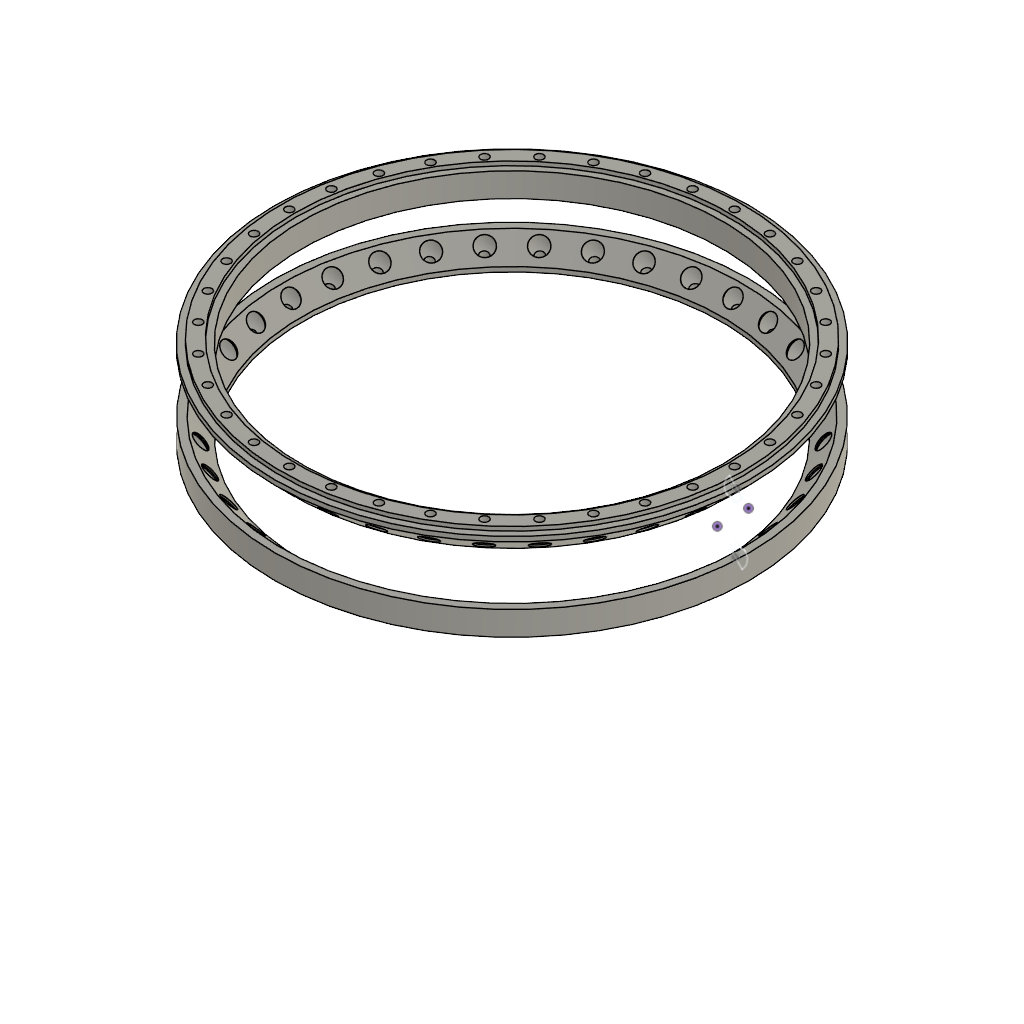
Robot_Assembly (Autodesk Fusion 360 archive; units mm, degrees)
design "Loziska"
part number: 2026-11-02-19-01-56-183
part number: 2026-11-02-19-01-56-425
part number: 2026-11-02-19-01-57-037
Autodesk Fusion 360 part; units mm, degrees
sketch "SK_Krouzek_dolni_telo" plane through (0, 0, 0) normal (0, 1, 0) x (1, 0, 0) in component "Krouzek_dolni"
  line L0 (53.5, -42) -> (57, -42)
  line L1 (57, -42) -> (57, -43)
  line L2 (57, -43) -> (58.55, -43)
  line L3 (58.55, -43) -> (58.55, -48.9576)
  line L4 (58.55, -48.9576) -> (56.6977, -48.9576)
  line L5 (56.6977, -48.9576) -> (51.9, -44.1598)
  line L6 (51.9, -44.1598) -> (51.9, -43)
  line L7 (51.9, -43) -> (53.5, -43)
  line L8 (53.5, -43) -> (53.5, -42)
  line L9 (0, -1.75) -> (0, -22.5) construction
  dimension "d22" = 53.5
  dimension "d23" = 42
  dimension "d24" = 57
  dimension "d25" = 57
  dimension "d26" = 43
  dimension "d27" = 58.55
  dimension "d28" = 43
  dimension "d29" = 58.55
  dimension "d30" = 48.9576
  dimension "d31" = 56.6977
  dimension "d32" = 48.9576
  dimension "d33" = 51.9
  dimension "d34" = 44.1598
  dimension "d35" = 51.9
  dimension "d36" = 43
  dimension "d37" = 43
  measures "d22" horizontal distance of origin L0.start
  measures "d23" vertical distance of origin L0.start
  measures "d24" horizontal distance of origin L0.end
  measures "d25" horizontal distance of origin L1.end
  measures "d26" vertical distance of origin L1.end
  measures "d27" horizontal distance of origin L2.end
  measures "d28" vertical distance of origin L2.end
  measures "d29" horizontal distance of origin L3.end
  measures "d30" vertical distance of origin L3.end
  measures "d31" horizontal distance of origin L4.end
  measures "d32" vertical distance of origin L4.end
  measures "d33" horizontal distance of origin L5.end
  measures "d34" vertical distance of origin L5.end
  measures "d35" horizontal distance of origin L6.end
  measures "d36" vertical distance of origin L6.end
  measures "d37" vertical distance of origin L7.end
revolve "Krouzek_dolni_telo" add sketch "SK_Krouzek_dolni_telo" angle 360 about axis through (0, 0, 1.75) along (0, 0, 1) makes body 1 in component "Krouzek_dolni"
sketch "SK_Krouzek_horni_telo" plane through (0, 0, 0) normal (0, 1, 0) x (1, 0, 0) in component "Krouzek_horni"
  line L0 (57, -65.6) -> (53.5, -65.6)
  line L1 (53.5, -65.6) -> (53.5, -64.6)
  line L2 (53.5, -64.6) -> (51.95, -64.6)
  line L3 (51.95, -64.6) -> (51.95, -58.6424)
  line L4 (51.95, -58.6424) -> (53.8023, -58.6424)
  line L5 (53.8023, -58.6424) -> (58.6, -63.4402)
  line L6 (58.6, -63.4402) -> (58.6, -64.6)
  line L7 (58.6, -64.6) -> (57, -64.6)
  line L8 (57, -64.6) -> (57, -65.6)
  line L9 (0, -1.75) -> (0, -22.5) construction
  dimension "d47" = 57
  dimension "d48" = 65.6
  dimension "d49" = 53.5
  dimension "d50" = 53.5
  dimension "d51" = 64.6
  dimension "d52" = 51.95
  dimension "d53" = 64.6
  dimension "d54" = 51.95
  dimension "d55" = 58.6424
  dimension "d56" = 53.8023
  dimension "d57" = 58.6424
  dimension "d58" = 58.6
  dimension "d59" = 63.4402
  dimension "d60" = 58.6
  dimension "d61" = 64.6
  dimension "d62" = 64.6
  measures "d47" horizontal distance of origin L0.start
  measures "d48" vertical distance of origin L0.start
  measures "d49" horizontal distance of origin L0.end
  measures "d50" horizontal distance of origin L1.end
  measures "d51" vertical distance of origin L1.end
  measures "d52" horizontal distance of origin L2.end
  measures "d53" vertical distance of origin L2.end
  measures "d54" horizontal distance of origin L3.end
  measures "d55" vertical distance of origin L3.end
  measures "d56" horizontal distance of origin L4.end
  measures "d57" vertical distance of origin L4.end
  measures "d58" horizontal distance of origin L5.end
  measures "d59" vertical distance of origin L5.end
  measures "d60" horizontal distance of origin L6.end
  measures "d61" vertical distance of origin L6.end
  measures "d62" vertical distance of origin L7.end
revolve "Krouzek_horni_telo" add sketch "SK_Krouzek_horni_telo" angle 360 about axis through (0, 0, 1.75) along (0, 0, 1) separate body makes body 2 in component "Krouzek_horni"
ref_plane "WorkPlane2" through (0, 0, 42) normal (0, 0, 1) x (1, 0, 0) in component "Krouzek_dolni"
sketch "SK_Vytlac" plane through (0, 0, 42) normal (0, 0, 1) x (1, 0, 0) in component "Krouzek_dolni"
  line L0 (0, 0) -> (55.55, 0) construction
  circle A0 centre (55.55, 0) radius 1
  dimension "d91" = 2
  dimension "d92" = 55.55
  constraint horizontal L0
  measures "d91" diameter of A0
  measures "d92" horizontal distance of L0.start L0.end
extrude "Vytlac_otvor" cut sketch "SK_Vytlac" along normal blind 4.18 bodies 1 in component "Krouzek_dolni"
pattern_circular "Vytlac_pole" count 36 over 360 about axis through (0, 0, 1.75) along (0, 0, 1) of "Vytlac_otvor" in component "Krouzek_dolni"
ref_plane "WorkPlane2" through (0, 0, 65.6) normal (0, 0, 1) x (1, 0, 0) in component "Krouzek_horni"
sketch "SK_Vytlac (2)" plane through (0, 0, 65.6) normal (0, 0, 1) x (1, 0, 0) in component "Krouzek_horni"
  line L0 (0, 0) -> (54.95, 0) construction
  circle A0 centre (54.95, 0) radius 1
  dimension "d99" = 2
  dimension "d100" = 54.95
  constraint horizontal L0
  measures "d99" diameter of A0
  measures "d100" horizontal distance of L0.start L0.end
extrude "Vytlac_otvor'" cut sketch "SK_Vytlac (2)" against normal blind 4.18 bodies 2 in component "Krouzek_horni"
pattern_circular "Vytlac_pole'" count 36 over 360 about axis through (0, 0, 1.75) along (0, 0, 1) of "Vytlac_otvor'" in component "Krouzek_horni"
ref_plane "WorkPlane3" through (0, 12.125, 0) normal (0.707107, 0, 0.707107) x (0, 1, 0) in component "Krouzek_dolni"
ref_plane "WorkPlane4" through (50.6788, 12.125, 50.6788) normal (0.707107, 0, 0.707107) x (0, 1, 0) in component "Krouzek_dolni"
sketch "SK_Kapsa_dolni" plane through (50.6788, 0, 50.6788) normal (0.707107, 0, 0.707107) x (0, 1, 0) in component "Krouzek_dolni"
  arc A0 (0, -8.6447) -> (2.48, -6.1647) centre (0, -6.1647) ccw
  line L0 (2.48, -6.1647) -> (2.48, -5.9031)
  line L1 (2.48, -5.9031) -> (2.05, -5.4731)
  line L2 (2.05, -5.4731) -> (2.05, -3.9731)
  line L3 (2.05, -3.9731) -> (0, -3.9731)
  line L4 (0, -3.9731) -> (0, -8.6447)
  dimension "d183" = 2.48
  dimension "d184" = 6.1647
  dimension "d187" = 2.05
  dimension "d231" = 0.2616
  dimension "d232" = 0.6916
  dimension "d233" = 2.1916
  constraint vertical L4
  constraint coincident A0.centre L4
  constraint tangent A0 L0
  constraint vertical L2
  constraint horizontal L3
  constraint coincident origin L4
  constraint vertical L0
  measures "d183" radius of A0
  measures "d184" vertical distance of origin A0.centre
  measures "d187" horizontal distance of origin L1.end
  measures "d231" vertical distance of A0.centre L0.end
  measures "d232" vertical distance of A0.centre L1.end
  measures "d233" vertical distance of A0.centre L3.end
revolve "Kapsa_dolni" cut sketch "SK_Kapsa_dolni" angle 360 about axis through (53.4882, 0, 47.8694) along (0.707107, 0, -0.707107) bodies 1 in component "Krouzek_dolni"
pattern_circular "Kapsy_pole" count 36 over 360 about axis through (0, 0, 1.75) along (0, 0, 1) of "Kapsa_dolni" in component "Krouzek_dolni"
ref_plane "WorkPlane3" through (0, 12.125, 0) normal (0.707107, 0, 0.707107) x (0, 1, 0) in component "Krouzek_horni"
ref_plane "WorkPlane4" through (58.3712, 12.125, 58.3712) normal (0.707107, 0, 0.707107) x (0, 1, 0) in component "Krouzek_horni"
sketch "SK_Kapsa_horni" plane through (58.3712, 0, 58.3712) normal (0.707107, 0, 0.707107) x (0, 1, 0) in component "Krouzek_horni"
  arc A0 (0, 6.5941) -> (-2.48, 4.1141) centre (0, 4.1141) ccw
  line L0 (-2.48, 4.1141) -> (-2.48, 3.8525)
  line L1 (-2.48, 3.8525) -> (-2.05, 3.4225)
  line L2 (-2.05, 3.4225) -> (-2.05, 1.9225)
  line L3 (-2.05, 1.9225) -> (0, 1.9225)
  line L4 (0, 1.9225) -> (0, 6.5941)
  dimension "d196" = 2.48
  dimension "d197" = 4.1141
  dimension "d200" = 2.05
  dimension "d234" = 0.2616
  dimension "d235" = 0.6916
  dimension "d236" = 2.1916
  constraint vertical L4
  constraint coincident A0.centre L4
  constraint tangent A0 L0
  constraint vertical L2
  constraint horizontal L3
  constraint coincident origin L4
  constraint vertical L0
  measures "d196" radius of A0
  measures "d197" vertical distance of origin A0.centre
  measures "d200" horizontal distance of origin L1.end
  measures "d234" vertical distance of A0.centre L0.end
  measures "d235" vertical distance of A0.centre L1.end
  measures "d236" vertical distance of A0.centre L3.end
revolve "Kapsa_horni" cut sketch "SK_Kapsa_horni" angle 360 about axis through (57.0118, 0, 59.7306) along (-0.707107, 0, 0.707107) bodies 2 in component "Krouzek_horni"
pattern_circular "Kapsy_pole'" count 36 over 360 about axis through (0, 0, 1.75) along (0, 0, 1) of "Kapsa_horni" in component "Krouzek_horni"
component "Krouzek_dolni" placed x (1, 0, 0) y (0, 1, 0) z (0, 0, 1) at (0, 0, 0)
component "Krouzek_horni" placed x (1, 0, 0) y (0, 1, 0) z (0, 0, 1) at (0, 0, 0)
equation "seat_plane_z = 42 mm" comment "dno drazky v Sedlu loziska (Base 2)"
equation "upper_seat_z = 65.6 mm" comment "dno drazky v Krytu hornim (Base 2)"
equation "ring_groove_d = 1 mm" comment "hloubka drazky = vyska jazyku krouzku"
equation "ring_id = 107 mm" comment "vnitrni prumer jazyku (drazka 106.4)"
equation "ring_wall = 3.5 mm" comment "sirka jazyku (drazka 4.1)"
equation "ball_d = 4.36 mm" comment "skutecny (namereny) prumer kulicky; drahy se nemeni, kapsy se prizpusobi"
equation "KrouzekDnoKapsy = 2 mm" comment "dno kapsy pro navrhovou kulicku DrahaBallD od dna drazky -> urcuje polohu drah v Base"
equation "KapsaVule = 0.6 mm" comment "vule kulove kapsy na prumer (kulicka se v kapse volne otaci)"
equation "KrouzekVule = KulickaR - KapsaUstiH" comment "kolma vule krouzek-draha = vycnivani kulicky lezici na dne kapsy"
equation "KrouzekVnitrR = 51.9 mm" comment "vnitrni polomer tela krouzku (dolni); horni zrcadlove"
equation "KrouzekVnejsiR = 58.55 mm" comment "vnejsi polomer tela krouzku (dolni); srouby M5 krytu od r 60.5"
equation "KrouzekPlochaNadStredem = 2.85 mm" comment "rovna cast nad stredem kulicky (strop kapsy min. 0.6 mm)"
equation "KulickyN = 36" comment "pocet kulicek v krouzku"
equation "KuzelUhel = 45 deg" comment "sklon drah (vzorce plati pro 45 st.)"
equation "KulickaR = ball_d / 2"
equation "KulickaDrahaR = ring_id / 2 + ring_wall / 2" comment "polomer drahy stredu kulicek"
equation "KulickaDolniZ = KulickaDrahaR + DrahaDolniC - KulickaR * sqrt(2)" comment "stred dolnich kulicek: kulicka ball_d se dotyka drahy rotoru (na polomeru KulickaDrahaR)"
equation "KulickaHorniZ = 2 * StredZ - KulickaDolniZ" comment "stred hornich kulicek, zrcadlove k dolnim (draha veze je zrcadlem drahy rotoru)"
equation "StredZ = ( seat_plane_z + upper_seat_z ) / 2" comment "stred symetrie dolni/horni krouzek"
equation "DrahaDolniC = seat_plane_z + KrouzekDnoKapsy + DrahaBallD / 2 - KulickaDrahaR + DrahaBallD / 2 * sqrt(2)" comment "draha rotoru z = r + C, pevne podle Base (kulicka DrahaBallD s dnem DrahaBallD/2 + KrouzekDnoKapsy nad drazkou)"
equation "KrouzekDolniC = DrahaDolniC - KrouzekVule * sqrt(2)" comment "horni plocha dolniho krouzku z = r + C"
equation "d22 = ring_id / 2"
equation "d23 = seat_plane_z"
equation "d24 = ring_id / 2 + ring_wall"
equation "d25 = ring_id / 2 + ring_wall"
equation "d26 = seat_plane_z + ring_groove_d"
equation "d27 = KrouzekVnejsiR"
equation "d28 = seat_plane_z + ring_groove_d"
equation "d29 = KrouzekVnejsiR"
equation "d30 = KulickaDolniZ + KrouzekPlochaNadStredem"
equation "d31 = KulickaDolniZ + KrouzekPlochaNadStredem - KrouzekDolniC"
equation "d32 = KulickaDolniZ + KrouzekPlochaNadStredem"
equation "d33 = KrouzekVnitrR"
equation "d34 = KrouzekVnitrR + KrouzekDolniC"
equation "d35 = KrouzekVnitrR"
equation "d36 = seat_plane_z + ring_groove_d"
equation "d37 = seat_plane_z + ring_groove_d"
equation "d47 = 2 * KulickaDrahaR - ( ring_id / 2 )"
equation "d48 = 2 * StredZ - ( seat_plane_z )"
equation "d49 = 2 * KulickaDrahaR - ( ring_id / 2 + ring_wall )"
equation "d50 = 2 * KulickaDrahaR - ( ring_id / 2 + ring_wall )"
equation "d51 = 2 * StredZ - ( seat_plane_z + ring_groove_d )"
equation "d52 = 2 * KulickaDrahaR - ( KrouzekVnejsiR )"
equation "d53 = 2 * StredZ - ( seat_plane_z + ring_groove_d )"
equation "d54 = 2 * KulickaDrahaR - ( KrouzekVnejsiR )"
equation "d55 = 2 * StredZ - ( KulickaDolniZ + KrouzekPlochaNadStredem )"
equation "d56 = 2 * KulickaDrahaR - ( KulickaDolniZ + KrouzekPlochaNadStredem - KrouzekDolniC )"
equation "d57 = 2 * StredZ - ( KulickaDolniZ + KrouzekPlochaNadStredem )"
equation "d58 = 2 * KulickaDrahaR - ( KrouzekVnitrR )"
equation "d59 = 2 * StredZ - ( KrouzekVnitrR + KrouzekDolniC )"
equation "d60 = 2 * KulickaDrahaR - ( KrouzekVnitrR )"
equation "d61 = 2 * StredZ - ( seat_plane_z + ring_groove_d )"
equation "d62 = 2 * StredZ - ( seat_plane_z + ring_groove_d )"
equation "UstiD = 4.1 mm" comment "prumer usti (hrana limce): kulicka se nacvakne, jde vytlacit"
equation "KapsaPosun = KapsaVule / 2" comment "stred kuloveho dna kapsy posunuty od stredu kulicky k draze (dno se dotyka kulicky)"
equation "VytlacD = 2 mm" comment "otvor ze spodu jazyku pro vytlaceni kulicky (spendlik/kancelarska sponka)"
equation "VytlacR = KulickaDrahaR + 0.3 mm" comment "polomer osy otvoru pro vytlaceni (mimo misto dotyku kulicka-dno)"
equation "d89 = seat_plane_z"
equation "d91 = VytlacD"
equation "d92 = VytlacR"
equation "d93 = KrouzekDnoKapsy + KulickaR"
equation "d95 = KulickyN"
equation "d97 = upper_seat_z"
equation "d99 = VytlacD"
equation "d100 = 2 * KulickaDrahaR - VytlacR"
equation "d101 = -( KrouzekDnoKapsy + KulickaR )"
equation "d103 = KulickyN"
equation "DrahaBallD = 4.3 mm" comment "navrhovy prumer kulicky, podle ktereho jsou drahy v Base_2_gears (ball_d tam = 4.3); NEMENIT bez zmeny Base"
equation "KapsaZdvih = 0.25 mm" comment "o kolik muze kulicka odjet ode dna kapsy k limci (vule k limci v provozu)"
equation "KapsaUstiH = KapsaZdvih + sqrt(KulickaR ^ 2 - ( UstiD / 2 ) ^ 2)" comment "rovina usti (plocha krouzku) od stredu kulicky ve smeru k draze"
equation "KapsaNadUsti = 1.5 mm" comment "presah rezu kapsy nad usti (jen vzduch)"
equation "d181 = ( KulickaDrahaR + KulickaDolniZ ) / sqrt(2)"
equation "d183 = ( ball_d + KapsaVule ) / 2"
equation "d184 = ( KulickaDrahaR - KulickaDolniZ ) / sqrt(2) - ( KapsaPosun )"
equation "d187 = UstiD / 2"
equation "d190 = KulickyN"
equation "d194 = ( KulickaDrahaR + KulickaHorniZ ) / sqrt(2)"
equation "d196 = ( ball_d + KapsaVule ) / 2"
equation "d197 = ( KulickaHorniZ - KulickaDrahaR ) / sqrt(2) - ( KapsaPosun )"
equation "d200 = UstiD / 2"
equation "d203 = KulickyN"
equation "d231 = KapsaUstiH - ( ( ball_d + KapsaVule ) / 2 - UstiD / 2 ) - KapsaPosun"
equation "d232 = KapsaUstiH - KapsaPosun"
equation "d233 = KapsaUstiH + KapsaNadUsti - KapsaPosun"
equation "d234 = KapsaUstiH - ( ( ball_d + KapsaVule ) / 2 - UstiD / 2 ) - KapsaPosun"
equation "d235 = KapsaUstiH - KapsaPosun"
equation "d236 = KapsaUstiH + KapsaNadUsti - KapsaPosun"
named bodies: "Krouzek_dolni", "Krouzek_horni"

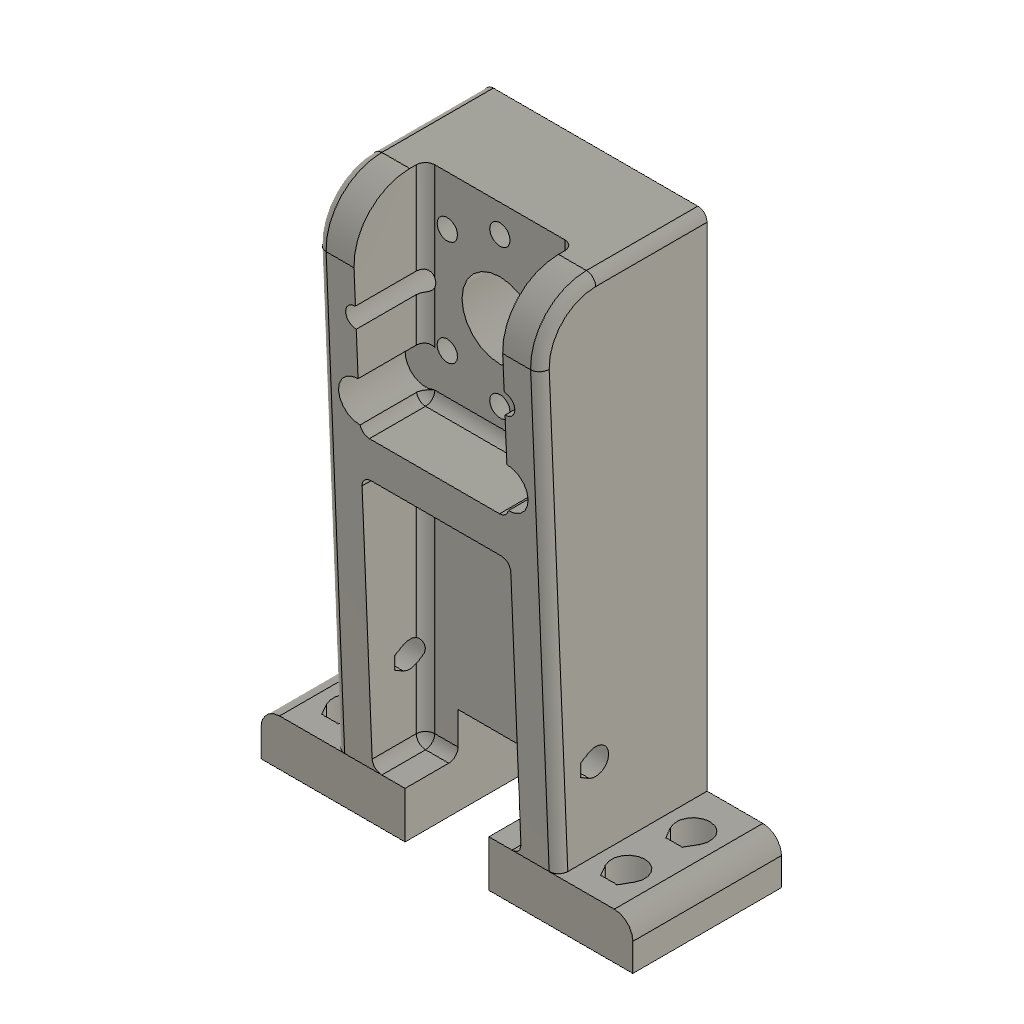
design "PenMountLink_V2"
Autodesk Fusion 360 part; units mm, degrees
sketch "SK_Zakladna" plane through (0, 0, 0) normal (0, 0, 1) x (1, 0, 0)
  line L0 (-20, -8) -> (20, -8)
  line L1 (20, -8) -> (20, 8)
  line L2 (20, 8) -> (-20, 8)
  line L3 (-20, 8) -> (-20, -8)
  dimension "d106" = 20
  dimension "d107" = 8
  dimension "d108" = 20
  dimension "d109" = 8
  constraint horizontal L0
  constraint vertical L1
  constraint horizontal L2
  constraint vertical L3
  measures "d106" horizontal distance of origin L0.start
  measures "d107" vertical distance of origin L0.start
  measures "d108" horizontal distance of origin L1.end
  measures "d109" vertical distance of origin L1.end
extrude "Zakladna" add sketch "SK_Zakladna" along normal blind 5
sketch "SK_Sloupek" plane through (0, 0, 0) normal (1, 0, 0) x (0, 0, -1)
  arc A0 (-59, -4) -> (-52.7496, -9.9948) centre (-53, -4) ccw
  line L0 (-5, 8) -> (-5, -8)
  line L1 (-5, -8) -> (-52.7496, -9.9948)
  line L2 (-59, -4) -> (-59, 8)
  line L3 (-59, 8) -> (-5, 8)
  dimension "d112" = 8
  dimension "d113" = 5
  dimension "d114" = 8
  dimension "d115" = 59
  dimension "d116" = 6
  dimension "d117" = 4
  constraint vertical L0
  constraint vertical L2
  constraint horizontal L3
  constraint tangent A0 L1
  constraint tangent A0 L2
  measures "d112" vertical distance of origin L0.start
  measures "d113" horizontal distance of origin L0.start
  measures "d114" vertical distance of origin L0.end
  measures "d115" horizontal distance of origin L2.end
  measures "d116" radius of A0
  measures "d117" vertical distance of origin A0.centre
extrude "Sloupek" add sketch "SK_Sloupek" along normal mid plane 24
sketch "SK_Kapsa" plane through (0, 0, 0) normal (0, 0, 1) x (1, 0, 0)
  line L0 (-8, -28) -> (8, -28)
  line L1 (8, -28) -> (8, -2.3)
  line L2 (8, -2.3) -> (-8, -2.3)
  line L3 (-8, -2.3) -> (-8, -28)
  dimension "d120" = 8
  dimension "d121" = 28
  dimension "d122" = 8
  dimension "d123" = -2.3
  constraint horizontal L0
  constraint vertical L1
  constraint horizontal L2
  constraint vertical L3
  measures "d120" horizontal distance of origin L0.start
  measures "d121" vertical distance of origin L0.start
  measures "d122" horizontal distance of origin L1.end
  measures "d123" vertical distance of origin L1.end
extrude "Kapsa_horni" cut sketch "SK_Kapsa" along normal through all from surface at 37
sketch "SK_Horn" plane through (0, 0, 0) normal (0, 1, 0) x (1, 0, 0)
  line L0 (0, 0) -> (0, -48) construction
  circle A0 centre (0, -48) radius 4.075
  line L1 (0, -48) -> (8, -48) construction
  line L2 (0, -48) -> (5.6569, -53.6569) construction
  circle A1 centre (5.6569, -53.6569) radius 1.1
  circle A2 centre (-5.6569, -53.6569) radius 1.1
  circle A3 centre (-5.6569, -42.3431) radius 1.1
  circle A4 centre (5.6569, -42.3431) radius 1.1
  dimension "d126" = 48
  dimension "d127" = 8.15
  dimension "d128" = 8
  dimension "d129" = 8
  dimension "d130" = 45
  dimension "d131" = 2.2
  constraint vertical L0
  constraint horizontal L1
  constraint equal A1 A2
  constraint equal A1 A3
  constraint equal A1 A4
  constraint symmetric L0 L2.end A2.centre
  constraint symmetric L1 A2.centre A3.centre
  constraint symmetric L1 L2.end A4.centre
  measures "d126" vertical distance of L0.start L0.end
  measures "d127" diameter of A0
  measures "d128" distance of L0.end L1.end
  measures "d129" distance of L0.end L2.end
  measures "d130" angle of L1 L2
  measures "d131" diameter of A1
extrude "Diry_horn" cut sketch "SK_Horn" along normal mid plane 26
sketch "SK_Diry_zavazi" plane through (0, 0, 0) normal (1, 0, 0) x (0, 0, -1)
  arc A0 (-12.5376, -4.7) -> (-14.9624, -4.7) centre (-13.75, -4) ccw
  line L0 (-14.9624, -4.7) -> (-14.437, -5.61)
  line L1 (-12.5376, -4.7) -> (-13.063, -5.61)
  line L2 (-14.437, -5.61) -> (-13.063, -5.61)
  line L3 (-13.75, -4) -> (-13.75, -5.61) construction
  dimension "d134" = 4
  dimension "d135" = 13.75
  dimension "d136" = 1.4
  dimension "d137" = 1.61
  dimension "d138" = 30
  constraint tangent A0 L0
  constraint tangent A0 L1
  constraint midpoint L2 L3.end
  constraint perpendicular L2 L3
  constraint vertical L3
  measures "d134" vertical distance of origin A0.centre
  measures "d135" horizontal distance of origin A0.centre
  measures "d136" radius of A0
  measures "d137" distance of A0.centre L3.end
  measures "d138" angle of L0 L3
extrude "Diry_zavazi" cut sketch "SK_Diry_zavazi" along normal mid plane 34
sketch "SK_Diry_zakladna" plane through (0, 0, 0) normal (0, 0, 1) x (1, 0, 0)
  arc A0 (-13.4412, -4.4) -> (-16.5588, -4.4) centre (-15, -3.5) ccw
  line L0 (-16.5588, -4.4) -> (-15.8833, -5.57)
  line L1 (-13.4412, -4.4) -> (-14.1167, -5.57)
  line L2 (-15.8833, -5.57) -> (-14.1167, -5.57)
  line L3 (-15, -3.5) -> (-15, -5.57) construction
  dimension "d141" = 15
  dimension "d142" = 3.5
  dimension "d143" = 1.8
  dimension "d144" = 2.07
  dimension "d145" = 30
  constraint tangent A0 L0
  constraint tangent A0 L1
  constraint midpoint L2 L3.end
  constraint perpendicular L2 L3
  constraint vertical L3
  measures "d141" horizontal distance of origin A0.centre
  measures "d142" vertical distance of origin A0.centre
  measures "d143" radius of A0
  measures "d144" distance of A0.centre L3.end
  measures "d145" angle of L0 L3
extrude "Dira_zakladna" cut sketch "SK_Diry_zakladna" along normal blind 6
pattern_linear "Diry_zakladna_pole" count 2 spacing 30 along (1, 0, 0) count 2 spacing 7 along (0, 1, 0) of "Dira_zakladna"
fillet "Usi_obvod_R" radius 1 6 edges at (-12, 2, 59) (-12, -8.3303, 57.1532) (-12, -8.9974, 28.8748) (12, 2, 59) (12, -8.3303, 57.1532) (12, -8.9974, 28.8748)
fillet "Zakladna_hrany_R" radius 2 2 edges at (-20, 0, 5) (20, 0, 5)
extrude "Kapsa_dolni" cut sketch "SK_Kapsa" along normal blind 28 from surface at 5
fillet "Kapsy_kouty_R" radius 1 13 edges at (8, -5.7349, 33) (8, -2.3, 19) (8, -5.15, 5) (0, -2.3, 5) (-8, -5.15, 5) (0, -2.3, 33) (-8, -2.3, 19) (-8, -5.7349, 33) (8, -2.3, 48) (8, -5.8184, 37) (0, -2.3, 37) (-8, -5.8184, 37) (-8, -2.3, 48)
sketch "SK_Horn_8" plane through (0, 0, 0) normal (0, 1, 0) x (1, 0, 0)
  circle A0 centre (8, -48) radius 1.1
  circle A1 centre (0, -56) radius 1.1
  circle A2 centre (-8, -48) radius 1.1
  circle A3 centre (0, -40) radius 1.1
  line L0 (0, -48) -> (8, -48) construction
  line L1 (0, -48) -> (0, -56) construction
  line L2 (0, -48) -> (-8, -48) construction
  line L3 (0, -48) -> (0, -40) construction
  dimension "d170" = 2.2
  dimension "d171" = 2.2
  dimension "d172" = 2.2
  dimension "d173" = 2.2
  dimension "d174" = 48
  dimension "d175" = 8
  dimension "d176" = 8
  dimension "d177" = 8
  dimension "d178" = 8
  constraint horizontal L0
  constraint vertical L1
  constraint horizontal L2
  constraint vertical L3
  measures "d170" diameter of A0
  measures "d171" diameter of A1
  measures "d172" diameter of A2
  measures "d173" diameter of A3
  measures "d174" vertical distance of origin L0.start
  measures "d175" horizontal distance of L0.start A0.centre
  measures "d176" vertical distance of L0.start A1.centre
  measures "d177" horizontal distance of L0.start A2.centre
  measures "d178" vertical distance of L0.start A3.centre
extrude "Diry_horn_8" cut sketch "SK_Horn_8" along normal mid plane 26
sketch "Sketch16" plane through (0, 8, 0) normal (0, 1, 0) x (-1, 0, 0)
  circle A0 centre (5.6569, 42.3431) radius 1.1
  circle A1 centre (5.6569, 53.6569) radius 1.1
  circle A2 centre (-5.6569, 53.6569) radius 1.1
  circle A3 centre (0, 48) radius 4.075
  circle A4 centre (-5.6569, 42.3431) radius 1.1
  arc A5 (-18, 5) -> (-20, 3) centre (-18, 3) ccw
  line L0 (-20, 3) -> (-20, 0)
  line L1 (-20, 0) -> (20, 0)
  line L2 (20, 0) -> (20, 3)
  arc A6 (20, 3) -> (18, 5) centre (18, 3) ccw
  line L3 (18, 5) -> (12, 5)
  line L4 (12, 5) -> (12, 58)
  arc A7 (12, 58) -> (11, 59) centre (11, 58) ccw
  line L5 (11, 59) -> (-11, 59)
  arc A8 (-11, 59) -> (-12, 58) centre (-11, 58) ccw
  line L6 (-12, 58) -> (-12, 5)
  line L7 (-12, 5) -> (-18, 5)
  line L8 (4.5, 9.5) -> (-4.5, 9.5)
  line L9 (-4.5, 9.5) -> (-4.5, -9.5)
  line L10 (-4.5, -9.5) -> (4.5, -9.5)
  line L11 (4.5, -9.5) -> (4.5, 9.5)
  line L12 (4.5, 9.5) -> (-4.5, -9.5) construction
  line L13 (-4.5, 9.5) -> (4.5, -9.5) construction
  circle A9 centre (0, 40) radius 1.1
  circle A10 centre (-8, 48) radius 1.1
  circle A11 centre (0, 56) radius 1.1
  circle A12 centre (8, 48) radius 1.1
  dimension "d167" = 9
  dimension "d168" = 19
  constraint horizontal L8
  constraint perpendicular L8 L9
  constraint parallel L8 L10
  constraint parallel L9 L11
  constraint coincident L12 origin
  constraint coincident L13 origin
  measures "d167" distance of L9.end L10.end
  measures "d168" distance of L8.end L9.end
extrude "Extrude13" cut sketch "Sketch16" against normal through all contours L1 L8 L9 L11
ref_plane "WorkPlane1" through (0, -2.3, 0) normal (0, 1, 0) x (0, 0, 1)
sketch "SK_Horn_8_hlavy" plane through (0, -2.3, 0) normal (0, 1, 0) x (1, 0, 0)
  circle A0 centre (8, -40) radius 2.2
  circle A1 centre (-8, -40) radius 2.2
  dimension "d186" = 4.4
  dimension "d187" = 4.4
  measures "d186" diameter of A0
  measures "d187" diameter of A1
extrude "Diry_horn_8_hlavy" cut sketch "SK_Horn_8_hlavy" against normal blind 21
equation "AxisOffset = 48 mm" comment "Osa motoru (horn) od dosedaci plochy zakladny z=0"
equation "BaseL = 40 mm" comment "Delka zakladny (X)"
equation "BaseD = 16 mm" comment "Hloubka zakladny (Y)"
equation "BaseT = 5 mm" comment "Tloustka zakladny"
equation "BaseHoleD = 3.6 mm" comment "Diry zakladny (M3)"
equation "BaseHoleX = 30 mm" comment "Roztec der zakladny X"
equation "BaseHoleY = 7 mm" comment "Roztec der zakladny Y"
equation "ColW = 24 mm" comment "Sirka sloupku (X)"
equation "ColD = BaseD" comment "Hloubka sloupku (Y)"
equation "WallT = 10.3 mm" comment "Stena hornu"
equation "PocketW = 16 mm" comment "Sirka kapsy na hlavy sroubu"
equation "ColTopAboveAxis = WeightHoleDZ + EarCornerR" comment "Vrsek sloupku nad osou"
equation "ColTopZ = AxisOffset + ColTopAboveAxis" comment "Vyska sloupku"
equation "EarCornerR = 6 mm" comment "Polomer predniho horniho rohu ucha"
equation "EarFrontExt = EarCornerR - ( WeightHoleFromHorn - ColD / 2 )" comment "Presah ucha pred celo zakladny"
equation "PocketBelowAxis = 11 mm" comment "Dno horni kapsy pod osou"
equation "HornCenterD = 8.15 mm" comment "Stredova dira hornu"
equation "HornHoleD = 2.2 mm" comment "Diry sroubu hornu M2"
equation "HornPCD = 16 mm" comment "Roztecna kruznice sroubu hornu"
equation "HornHoleCham = 0.5 mm" comment "Srazeni der hornu v kapse"
equation "WeightHoleD = 2.8 mm" comment "Diry pro zavazi"
equation "WeightHoleFromHorn = 12 mm" comment "Diry zavazi: vzdalenost pred celem hornu"
equation "WeightHoleDZ = 5 mm" comment "Diry zavazi: posun nad osou"
equation "TdHalfAngle = 30 deg" comment "Slzicka: polovicni uhel spicky"
equation "TdCapRatio = 1.15" comment "Slzicka: vzdalenost useku spicky / polomer"
equation "R_EarOuter = 1 mm" comment "Zaobleni vnejsiho obvodu usi"
equation "R_ColRoot = 1 mm" comment "Zaobleni korene sloupku"
equation "R_BaseEdge = 2 mm" comment "Zaobleni hran zakladny"
equation "d106 = BaseL / 2"
equation "d107 = BaseD / 2"
equation "d108 = BaseL / 2"
equation "d109 = BaseD / 2"
equation "d110 = BaseT"
equation "d112 = ColD / 2"
equation "d113 = BaseT"
equation "d114 = ColD / 2"
equation "d115 = ColTopZ"
equation "d116 = EarCornerR"
equation "d117 = ColD / 2 + EarFrontExt - EarCornerR"
equation "d118 = ColW"
equation "d120 = PocketW / 2"
equation "d121 = ColD / 2 + 20 mm"
equation "d122 = PocketW / 2"
equation "d123 = ColD / 2 - WallT"
equation "d124 = AxisOffset - PocketBelowAxis"
equation "d126 = AxisOffset"
equation "d127 = HornCenterD"
equation "d128 = HornPCD / 2"
equation "d129 = HornPCD / 2"
equation "d131 = HornHoleD"
equation "d132 = ColD + 10 mm"
equation "d134 = WeightHoleFromHorn - ColD / 2"
equation "d136 = WeightHoleD / 2"
equation "d137 = ( WeightHoleD / 2 ) * TdCapRatio"
equation "d138 = TdHalfAngle"
equation "d139 = ColW + 10 mm"
equation "d141 = BaseHoleX / 2"
equation "d142 = BaseHoleY / 2"
equation "d143 = BaseHoleD / 2"
equation "d144 = ( BaseHoleD / 2 ) * TdCapRatio"
equation "d145 = TdHalfAngle"
equation "d146 = BaseT + 1 mm"
equation "d150 = BaseHoleX"
equation "d151 = BaseHoleY"
equation "d153 = R_EarOuter"
equation "d157 = R_BaseEdge"
equation "RibT = 4 mm" comment "Zebro mezi kapsami (pod srouby hornu)"
equation "R_PocketCorner = 1 mm" comment "Zaobleni vnitrnich koutu kapes"
equation "d161 = BaseT"
equation "d162 = AxisOffset - PocketBelowAxis - RibT - BaseT"
equation "d165 = R_PocketCorner"
equation "d170 = HornHoleD"
equation "d171 = HornHoleD"
equation "d172 = HornHoleD"
equation "d173 = HornHoleD"
equation "d174 = AxisOffset"
equation "d175 = HornPCD / 2"
equation "d176 = HornPCD / 2"
equation "d177 = HornPCD / 2"
equation "d178 = HornPCD / 2"
equation "d179 = ColD + 10 mm"
equation "d183 = ColD / 2 - WallT"
equation "HornHeadReliefD = 4.4 mm" comment "Vybrani pro hlavy M2 u bocnich der hornu"
equation "d186 = HornHeadReliefD"
equation "d187 = HornHeadReliefD"
equation "d188 = -( ColD + 5 mm )"
named bodies: "PenMountLink"

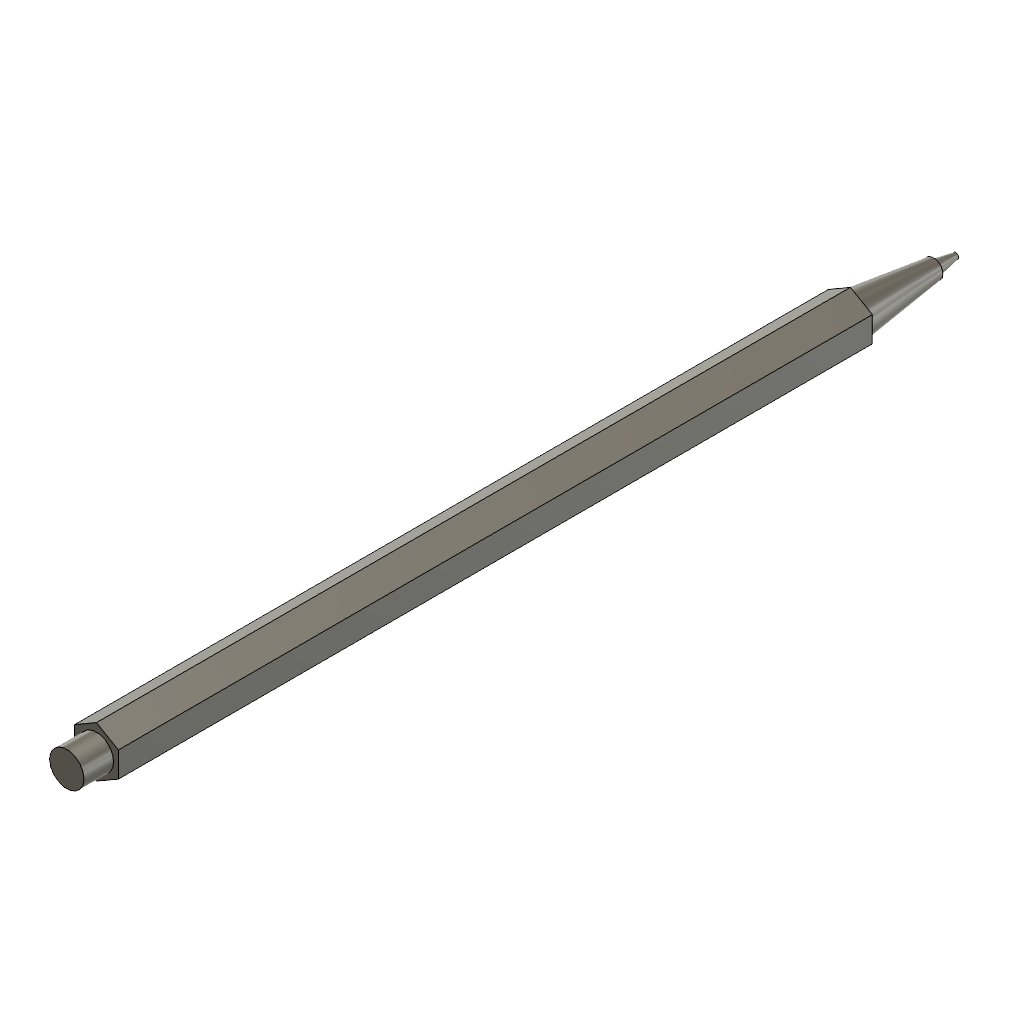
design "Pero"
part number: 2026-11-02-16-26-47-575
Autodesk Fusion 360 part; units mm, degrees
sketch "Hrot_profil" plane through (0, 0, 0) normal (0, 1, 0) x (1, 0, 0)
  line L0 (0, 0) -> (0.5, -0.25)
  line L1 (0.5, -0.25) -> (1.2, -4)
  line L2 (1.2, -4) -> (1.6, -4)
  line L3 (1.6, -4) -> (3.4, -18)
  line L4 (3.4, -18) -> (0, -18)
  line L5 (0, -18) -> (0, 0)
revolve "Hrot" add sketch "Hrot_profil" angle 360 about axis through (0, 0, 1.75) along (0, 0, 1)
ref_plane "WorkPlane1" through (0, 0, 18) normal (0, 0, 1) x (1, 0, 0)
sketch "Telo_sestihran" plane through (0, 0, 18) normal (0, 0, 1) x (1, 0, 0)
  line L0 (3.7, 2.1362) -> (0, 4.2724)
  line L1 (0, 4.2724) -> (-3.7, 2.1362)
  line L2 (-3.7, 2.1362) -> (-3.7, -2.1362)
  line L3 (-3.7, -2.1362) -> (0, -4.2724)
  line L4 (0, -4.2724) -> (3.7, -2.1362)
  line L5 (3.7, -2.1362) -> (3.7, 2.1362)
extrude "Telo" add sketch "Telo_sestihran" along normal blind 127
ref_plane "WorkPlane2" through (0, 0, 145) normal (0, 0, 1) x (1, 0, 0)
sketch "Zatka_profil" plane through (0, 0, 145) normal (0, 0, 1) x (1, 0, 0)
  circle A0 centre (0, 0) radius 2.9
extrude "Zatka" add sketch "Zatka_profil" along normal blind 5
equation "DelkaPera = 150 mm" comment "Celkova delka pera (hrot -> konec)"
equation "HexAF = 7.4 mm" comment "Sestihran tela pres plochy (sedi do drazky Pen_mount)"
equation "DelkaKuzele = 18 mm" comment "Delka predni kuzelove casti vcetne hrotu"
equation "DelkaZatky = 5 mm" comment "Delka zadni zatky"
equation "d6 = DelkaKuzele"
equation "d8 = DelkaPera - DelkaKuzele - DelkaZatky"
equation "d10 = DelkaPera - DelkaZatky"
equation "d12 = DelkaZatky"
named bodies: "Pero"

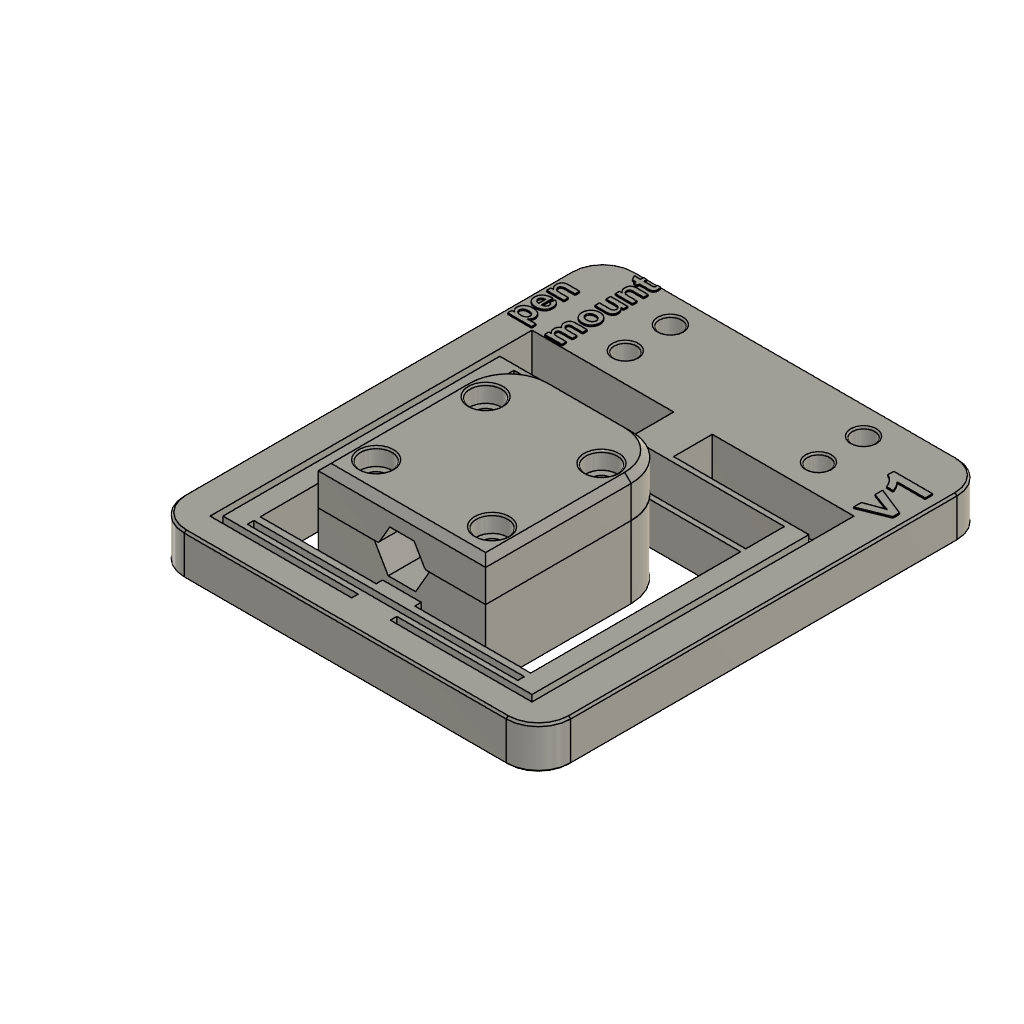
design "Pen_mount"
Autodesk Fusion 360 part; units mm, degrees
sketch "Mount" plane through (0, 0, 0) normal (0, 0, 1) x (1, 0, 0) in component "Pen Mount"
  line L0 (30, -35) -> (-30, -35)
  line L1 (-30, -35) -> (-30, 35)
  line L2 (-30, 35) -> (30, 35)
  line L3 (30, 35) -> (30, -35)
  line L4 (30, -35) -> (-30, 35) construction
  line L5 (-30, -35) -> (30, 35) construction
  line L6 (25, 19) -> (25, -31)
  line L7 (-25, -31) -> (-25, 19)
  line L8 (0, 19) -> (0, -31) construction
  line L9 (0, 35) -> (0, -35) construction
  line L10 (24, 13) -> (24, -30)
  line L11 (-24, -30) -> (-24, 13)
  line L12 (-21, 12.2) -> (21, 12.2)
  line L13 (21, -29.2) -> (-21, -29.2)
  line L14 (-3, 13) -> (-3, 19)
  line L15 (3, 13) -> (3, 19)
  line L16 (-3, -30) -> (-3, -31)
  line L17 (3, -30) -> (3, -31)
  line L18 (24, -30) -> (3, -30)
  line L19 (-3, -30) -> (-24, -30)
  line L20 (-24, 13) -> (-3, 13)
  line L21 (3, 13) -> (24, 13)
  line L22 (-21, -27.2) -> (-3, -27.2)
  line L23 (-3, -27.2) -> (-3, -26.2)
  line L24 (-3, -26.2) -> (-13, -26.2)
  line L25 (-13, -26.2) -> (-13, -3.6)
  line L26 (-6, 3.4) -> (-3, 3.4)
  line L27 (-3, 3.4) -> (-3, 5.4)
  line L28 (-3, 5.4) -> (-21, 5.4)
  line L29 (-21, -28.2) -> (0, -28.2)
  line L30 (-21, 6.2) -> (0, 6.2)
  line L31 (-21, 6.2) -> (-21, 12.2)
  line L32 (-21, -29.2) -> (-21, -28.2)
  line L33 (-21, -27.2) -> (-21, 5.4)
  line L34 (21, 6.2) -> (21, 12.2)
  line L35 (21, 6.2) -> (0, 6.2)
  line L36 (3, 5.4) -> (21, 5.4)
  line L37 (3, 3.4) -> (3, 5.4)
  line L38 (6, 3.4) -> (3, 3.4)
  line L39 (13, -26.2) -> (13, -3.6)
  line L40 (21, -27.2) -> (21, 5.4)
  line L41 (3, -26.2) -> (13, -26.2)
  line L42 (3, -27.2) -> (3, -26.2)
  line L43 (21, -27.2) -> (3, -27.2)
  line L44 (21, -28.2) -> (0, -28.2)
  line L45 (21, -29.2) -> (21, -28.2)
  line L46 (-25, 19) -> (-3, 19)
  line L47 (3, 19) -> (25, 19)
  line L48 (25, -31) -> (3, -31)
  line L49 (-3, -31) -> (-25, -31)
  arc A0 (-6, 3.4) -> (-13, -3.6) centre (-6, -3.6) ccw
  arc A1 (13, -3.6) -> (6, 3.4) centre (6, -3.6) ccw
  circle A2 centre (-9, -4.2) radius 1.15
  circle A3 centre (-9, -21.2) radius 1.15
  line L50 (-9, -4.2) -> (-9, -21.2) construction
  circle A4 centre (9, -4.2) radius 1.15
  line L51 (9, -4.2) -> (9, -21.2) construction
  circle A5 centre (9, -21.2) radius 1.15
  circle A6 centre (-15, 30.5) radius 1.75
  line L52 (-15, 30.5) -> (-15, 23.5) construction
  circle A7 centre (-15, 23.5) radius 1.75
  circle A8 centre (15, 30.5) radius 1.75
  line L53 (15, 30.5) -> (15, 23.5) construction
  circle A9 centre (15, 23.5) radius 1.75
  line L54 (-4.2665, 3.4) -> (-4.2665, -26.2)
  line L55 (4.2665, 3.4) -> (4.2665, -26.2)
  line L56 (-3, 3.4) -> (3, 3.4)
  line L57 (-3, -26.2) -> (3, -26.2)
  dimension "d1" = 60
  dimension "d2" = 70
  dimension "d3" = 5
  dimension "d4" = 4
  dimension "d5" = 50
  dimension "d6" = 6
  dimension "d7" = 6
  dimension "d8" = 0.8
  dimension "d9" = 0.8
  dimension "d11" = 3
  dimension "d12" = 6
  dimension "d13" = 1
  dimension "d14" = 1
  dimension "d16" = 1
  dimension "d17" = 1
  dimension "d18" = 1
  dimension "d19" = 2
  dimension "d20" = 0.8
  dimension "d22" = 6
  dimension "d23" = 26
  dimension "d24" = 7
  dimension "d25" = 2.3
  dimension "d27" = 17
  dimension "d28" = 5
  dimension "d29" = 18
  dimension "d30" = 4
  dimension "d32" = 3.5
  dimension "d34" = 4.5
  dimension "d35" = 4.5
  dimension "d40" = 4.2665
  dimension "d73" = 30
  dimension "d74" = 7
  constraint horizontal L0
  constraint perpendicular L0 L1
  constraint parallel L0 L2
  constraint parallel L1 L3
  constraint coincident L4 origin
  constraint coincident L5 origin
  constraint horizontal L46
  constraint vertical L6
  constraint horizontal L48
  constraint vertical L7
  constraint midpoint L2 L9.start
  constraint midpoint L0 L9.end
  constraint collinear L8 L9
  constraint horizontal L20
  constraint vertical L10
  constraint horizontal L18
  constraint vertical L11
  constraint horizontal L12
  constraint horizontal L13
  constraint vertical L32
  constraint perpendicular L14 L46
  constraint symmetric L9 L14.start L15.start
  constraint symmetric L9 L14.end L15.end
  constraint coincident L16.start L18
  constraint coincident L16.end L48
  constraint perpendicular L16 L48
  constraint symmetric L9 L16.start L17.start
  constraint symmetric L9 L16.end L17.end
  constraint collinear L18 L19
  constraint collinear L20 L21
  constraint coincident L22.start L32
  constraint perpendicular L22 L32
  constraint perpendicular L22 L23
  constraint perpendicular L23 L24
  constraint perpendicular L24 L25
  constraint perpendicular L23 L26
  constraint perpendicular L26 L27
  constraint perpendicular L28 L32
  constraint horizontal L29
  constraint coincident L8 L29.end
  constraint coincident L9 L29.end
  constraint horizontal L30
  constraint coincident L30.start L32
  constraint coincident L8 L30.end
  constraint collinear L16 L23
  constraint collinear L14 L27
  constraint collinear L31 L32
  constraint collinear L32 L33
  constraint symmetric L8 L12.start L12.end
  constraint symmetric L8 L13.end L13.start
  constraint symmetric L8 L22.start L40.start
  constraint symmetric L8 L22.end L42.start
  constraint symmetric L8 L23.end L41.start
  constraint symmetric L8 L24.end L39.start
  constraint symmetric L8 L26.end L37.start
  constraint symmetric L8 L27.end L36.start
  constraint symmetric L8 L28.end L36.end
  constraint symmetric L8 L29.start L44.start
  constraint symmetric L8 L29.end L44.end
  constraint symmetric L8 L30.start L34.start
  constraint symmetric L8 L30.end L35.end
  constraint collinear L46 L47
  constraint coincident L8.start L46
  constraint collinear L48 L49
  constraint tangent L26 A0
  constraint tangent L25 A0
  constraint tangent L38 A1
  constraint tangent L39 A1
  constraint equal A0 A1
  constraint perpendicular L37 L38
  constraint equal A2 A3
  constraint coincident A2.centre L50.start
  constraint coincident A3.centre L50.end
  constraint vertical L50
  constraint symmetric L9 A2 A4
  constraint symmetric L9 A3 A5
  constraint symmetric L9 A2.centre A4.centre
  constraint symmetric L9 A3.centre L51.end
  constraint coincident L12.end L34.end
  constraint coincident L13.start L45.start
  constraint coincident A6.centre L52.start
  constraint vertical L52
  constraint coincident L52.end A7.centre
  constraint equal A6 A7
  constraint symmetric L9 A6 A8
  constraint symmetric L9 A6.centre A8.centre
  constraint symmetric L9 L52.end L53.end
  constraint symmetric L9 A7 A9
  constraint coincident L26 L54.start
  constraint coincident L24 L54.end
  constraint perpendicular L24 L54
  constraint symmetric L9 L54.start L55.start
  constraint symmetric L9 L54.end L55.end
  measures "d1" distance of L1.end L2.end
  measures "d2" distance of L0.end L1.end
  measures "d3" distance of L1 L7
  measures "d4" distance of L0 L48
  measures "d5" distance of L6.start L6.end
  measures "d6" distance of L14 L15
  measures "d7" distance of L16 L17
  measures "d8" distance of L12 L20
  measures "d9" distance of L13 L18
  measures "d11" distance of L11 L32
  measures "d12" distance of L14.start L14.end
  measures "d13" distance of L16.start L16.end
  measures "d14" distance of L7 L11
  measures "d16" distance of L13 L29
  measures "d17" distance of L22 L29
  measures "d18" distance of L22.end L23.end
  measures "d19" distance of L26.end L27.end
  measures "d20" distance of L28 L30
  measures "d22" distance of L12 L30
  measures "d23" distance of L25 L39
  measures "d24" radius of A0
  measures "d25" diameter of A2
  measures "d27" distance of A2.centre A3.centre
  measures "d28" distance of L24 A3.centre
  measures "d29" distance of L50 L51
  measures "d30" distance of L25 L50
  measures "d32" diameter of A6
  measures "d34" distance of L2 A6.centre
  measures "d35" distance of L46 L52.end
  measures "d40" distance of L9 L54
  measures "d73" distance of L52 L53
  measures "d74" distance of A6.centre L52.end
extrude "Extrude1" add sketch "Mount" along normal blind 6.5 contours L0 L1 L2 L3 | L24 L26 L38 L41 L54 L55 L56 L57 | L24 L25 L26 A0 L54 | L38 L39 L41 A1 L55 makes body 1 in component "Pen Mount"
extrude "Extrude3" add sketch "Mount" along normal blind 1 from surface at 6.5 contours L24 L26 L38 L41 L54 L55 L56 L57 | L24 L25 L26 A0 L54 | L38 L39 L41 A1 L55 bodies 1 in component "Pen Mount"
extrude "Extrude2" add sketch "Mount" along normal blind 3.695 from surface at 7.5 contours L24 L25 L26 A0 L54 | L38 L39 L41 A1 L55 bodies 1 in component "Pen Mount"
sketch "Sketch1" plane through (0, 0, 11.195) normal (0, 0, 1) x (-1, 0, 0) in component "Clamp"
  line L0 (4.2665, -3.4) -> (6, -3.4)
  arc A0 (6, -3.4) -> (13, 3.6) centre (6, 3.6) ccw
  line L1 (13, 3.6) -> (13, 26.2)
  line L2 (13, 26.2) -> (4.2665, 26.2)
  line L3 (4.2665, 26.2) -> (4.2665, -3.4)
  circle A1 centre (9, 4.2) radius 1.15
  circle A2 centre (9, 21.2) radius 1.15
  line L4 (4.2665, -3.4) -> (4.2665, 26.2)
  line L5 (4.2665, 26.2) -> (-4.2665, 26.2)
  line L6 (-4.2665, 26.2) -> (-4.2665, -3.4)
  line L7 (-4.2665, -3.4) -> (4.2665, -3.4)
  line L8 (-6, -3.4) -> (-4.2665, -3.4)
  line L9 (-4.2665, -3.4) -> (-4.2665, 26.2)
  line L10 (-4.2665, 26.2) -> (-13, 26.2)
  line L11 (-13, 26.2) -> (-13, 3.6)
  arc A3 (-13, 3.6) -> (-6, -3.4) centre (-6, 3.6) ccw
  circle A4 centre (-9, 4.2) radius 1.15
  circle A5 centre (-9, 21.2) radius 1.15
  line L12 (-3.6165, -3.4) -> (-3.6165, 26.2)
  line L13 (0, -3.4) -> (0, 26.2) construction
  line L14 (3.6165, -3.4) -> (3.6165, 26.2)
  circle A6 centre (9, 4.2) radius 1.48
  circle A7 centre (-9, 4.2) radius 1.48
  circle A8 centre (-9, 21.2) radius 1.48
  circle A9 centre (9, 21.2) radius 1.48
  dimension "d64" = 0.65
  dimension "d75" = 0.33
  constraint coincident L7 L12.start
  constraint coincident L5 L12.end
  constraint perpendicular L5 L12
  constraint midpoint L7 L13.start
  constraint midpoint L5 L13.end
  constraint symmetric L12.start L13 L14.start
  constraint symmetric L12.end L13 L14.end
  constraint concentric A4 A7
  constraint concentric A5 A8
  constraint concentric A2 A9
  constraint equal A6 A9
  constraint equal A6 A7
  constraint equal A6 A8
  measures "d64" distance of L6 L12
extrude "Extrude1'" add sketch "Sketch1" along normal blind 3 from surface at 2.995 separate body contours L5 L7 L12 L14 makes body 2 in component "Clamp"
extrude "Extrude2'" add sketch "Sketch1" along normal blind 5.995 contours L0 A0 L1 L2 L3 L4 | L3 L4 L5 L7 L14 | L5 L6 L7 L9 L12 | L6 L8 L9 L10 L11 A3 bodies 2 in component "Clamp"
draft "Draft1" angle 30 neutral plane through (0, 0, 11.195) pull (0, 0, -1) 1 faces at (3.6165, -6.4667, 12.1933) on bodies 2 in component "Clamp"
draft "Draft2" angle 30 neutral plane through (0, 0, 11.195) pull (0, 0, -1) 1 faces at (-3.6165, -6.4667, 12.1933) on bodies 2 in component "Clamp"
sketch "Sketch2" plane through (0, 0, 17.19) normal (0, 0, 1) x (-1, 0, 0) in component "Clamp"
  line L0 (13, 26.2) -> (-13, 26.2)
  line L1 (-6, -3.4) -> (6, -3.4)
  circle A0 centre (9, 21.2) radius 2.45
  circle A1 centre (9, 4.2) radius 2.45
  circle A2 centre (-9, 4.2) radius 2.45
  circle A3 centre (-9, 21.2) radius 2.45
  arc A4 (6, -3.4) -> (13, 3.6) centre (6, 3.6) ccw
  line L2 (13, 3.6) -> (13, 26.2)
  line L3 (-13, 26.2) -> (-13, 3.6)
  arc A5 (-13, 3.6) -> (-6, -3.4) centre (-6, 3.6) ccw
  circle A6 centre (9, 21.2) radius 1.48
  circle A7 centre (9, 4.2) radius 1.48
  circle A8 centre (-9, 21.2) radius 1.48
  circle A9 centre (-9, 4.2) radius 1.48
  dimension "d53" = 4.9
  constraint equal A0 A1
  constraint equal A0 A2
  constraint equal A0 A3
  constraint concentric A1 A7
  constraint concentric A2 A9
  constraint concentric A3 A8
  constraint concentric A0 A6
  measures "d53" diameter of A0
extrude "Extrude3'" cut sketch "Sketch2" against normal blind 2.65 contours A0 | A1 | A2 | A3 | A6 | A7 | A8 | A9 bodies 2 in component "Clamp"
chamfer "Chamfer1" distance 1 angle 45 6 edges at (0, 3.4, 17.19) (10.9497, 1.3497, 17.19) (13, -14.9, 17.19) (-13, -14.9, 17.19) (-10.9497, 1.3497, 17.19) (0, -26.2, 17.19) tangent chain off on bodies 2 in component "Clamp"
draft "Draft1'" angle 30 neutral plane through (0, 0, 11.195) pull (0, 0, 1) 1 faces at (-4.2665, -16.3333, 9.9633) on bodies 1 in component "Pen Mount"
draft "Draft2'" angle 30 neutral plane through (0, 0, 11.195) pull (0, 0, 1) 1 faces at (4.2665, -16.3333, 9.9633) on bodies 1 in component "Pen Mount"
fillet "Fillet1" radius 5 4 edges at (-30, -35, 3.25) (30, -35, 3.25) (30, 35, 3.25) (-30, 35, 3.25) on bodies 1 in component "Pen Mount"
chamfer "Chamfer1'" distance 0.3 angle 45 16 edges at (30, 0, 0) (28.5355, -33.5355, 0) (0, -35, 0) (-28.5355, -33.5355, 0) (-30, 0, 0) (-28.5355, 33.5355, 0) (0, 35, 0) (28.5355, 33.5355, 0) (30, 0, 6.5) (28.5355, 33.5355, 6.5) (0, 35, 6.5) (-28.5355, 33.5355, 6.5) (-30, 0, 6.5) (-28.5355, -33.5355, 6.5) (0, -35, 6.5) (28.5355, -33.5355, 6.5) tangent chain off on bodies 1 in component "Pen Mount"
sketch "Pen cross section" plane through (0, -26.2, 0) normal (0, -1, 0) x (1, 0, 0) in component "Pen Mount"
  line L0 (3, 0) -> (13, 0)
  line L1 (13, 0) -> (13, 11.195)
  line L2 (13, 11.195) -> (4.2665, 11.195)
  line L3 (4.2665, 11.195) -> (2.1332, 7.5)
  line L4 (2.1332, 7.5) -> (-2.1332, 7.5)
  line L5 (-2.1332, 7.5) -> (-4.2665, 11.195)
  line L6 (-4.2665, 11.195) -> (-13, 11.195)
  line L7 (-13, 11.195) -> (-13, 0)
  line L8 (-13, 0) -> (-3, 0)
  line L9 (-3, 0) -> (-3, 6.5)
  line L10 (-3, 6.5) -> (3, 6.5)
  line L11 (3, 6.5) -> (3, 0)
  line L12 (-2.1333, 7.5) -> (2.1333, 7.5)
  line L13 (2.1333, 7.5) -> (4.2666, 11.195)
  line L14 (4.2666, 11.195) -> (2.1333, 14.89)
  line L15 (2.1333, 14.89) -> (-2.1333, 14.89)
  line L16 (-2.1333, 14.89) -> (-4.2666, 11.195)
  line L17 (-4.2666, 11.195) -> (-2.1333, 7.5)
  line L18 (0, 14.89) -> (0, 7.5) construction
  point P0 (0, 11.195)
  dimension "d69" = 8.5332
  dimension "d70" = 7.39
  constraint collinear L4 L12
  constraint midpoint L15 L18.start
  constraint midpoint L12 L18.end
  constraint midpoint L4 L18.end
  measures "d69" distance of L13.end L16.end
  measures "d70" distance of L12 L15
fillet "Fillet1'" radius 0.5 2 edges at (-3.6165, -11.4, 11.195) (3.6165, -11.4, 11.195) on bodies 2 in component "Clamp"
sketch "Mounting screw heads" plane through (0, 0, 6.5) normal (0, 0, 1) x (-1, 0, 0) in component "Pen Mount"
  circle A0 centre (-15, -23.5) radius 1.75
  circle A1 centre (-15, -30.5) radius 1.75
  circle A2 centre (15, -23.5) radius 1.75
  circle A3 centre (15, -30.5) radius 1.75
  line L0 (-21, 29.2) -> (21, 29.2)
  line L1 (21, 29.2) -> (21, 28.2)
  line L2 (21, 28.2) -> (-21, 28.2)
  line L3 (-21, 28.2) -> (-21, 29.2)
  line L4 (-21, -6.2) -> (21, -6.2)
  line L5 (21, -6.2) -> (21, -12.2)
  line L6 (21, -12.2) -> (-21, -12.2)
  line L7 (-21, -12.2) -> (-21, -6.2)
  line L8 (24, 30) -> (3, 30)
  line L9 (3, 30) -> (3, 31)
  line L10 (3, 31) -> (25, 31)
  line L11 (25, 31) -> (25, -19)
  line L12 (25, -19) -> (3, -19)
  line L13 (3, -19) -> (3, -13)
  line L14 (3, -13) -> (24, -13)
  line L15 (24, -13) -> (24, 30)
  line L16 (-3, 26.2) -> (3, 26.2)
  line L17 (3, 26.2) -> (3, 27.2)
  line L18 (3, 27.2) -> (21, 27.2)
  line L19 (21, 27.2) -> (21, -5.4)
  line L20 (21, -5.4) -> (3, -5.4)
  line L21 (3, -5.4) -> (3, -3.4)
  line L22 (3, -3.4) -> (-3, -3.4)
  line L23 (-3, -3.4) -> (-3, -5.4)
  line L24 (-3, -5.4) -> (-21, -5.4)
  line L25 (-21, -5.4) -> (-21, 27.2)
  line L26 (-21, 27.2) -> (-3, 27.2)
  line L27 (-3, 27.2) -> (-3, 26.2)
  line L28 (-24, -13) -> (-3, -13)
  line L29 (-3, -13) -> (-3, -19)
  line L30 (-3, -19) -> (-25, -19)
  line L31 (-25, -19) -> (-25, 31)
  line L32 (-25, 31) -> (-3, 31)
  line L33 (-3, 31) -> (-3, 30)
  line L34 (-3, 30) -> (-24, 30)
  line L35 (-24, 30) -> (-24, -13)
  line L36 (29.7, -30) -> (29.7, 30)
  arc A4 (29.7, 30) -> (25, 34.7) centre (25, 30) ccw
  line L37 (25, 34.7) -> (-25, 34.7)
  arc A5 (-25, 34.7) -> (-29.7, 30) centre (-25, 30) ccw
  line L38 (-29.7, 30) -> (-29.7, -30)
  arc A6 (-29.7, -30) -> (-25, -34.7) centre (-25, -30) ccw
  line L39 (-25, -34.7) -> (25, -34.7)
  arc A7 (25, -34.7) -> (29.7, -30) centre (25, -30) ccw
  circle A8 centre (15, -30.5) radius 3
  circle A9 centre (15, -23.5) radius 3
  circle A10 centre (-15, -30.5) radius 3
  circle A11 centre (-15, -23.5) radius 3
  line L40 (-27.7, -20) -> (-27.7, -33.2) construction
  line L41 (-27.7, -33.2) -> (-22.2993, -33.2) construction
  line L42 (-22.2993, -33.2) -> (-22.2993, -20) construction
  line L43 (-22.2993, -20) -> (-27.7, -20) construction
  line L44 (24.0828, -19.2154) -> (24.0761, -31.7956) construction
  line L45 (24.0761, -31.7956) -> (29.0761, -31.7983) construction
  line L46 (29.0761, -31.7983) -> (29.0828, -19.2181) construction
  line L47 (29.0828, -19.2181) -> (24.0828, -19.2154) construction
  dimension "d76" = 6
  dimension "d87" = 6
  dimension "d88" = 1
  dimension "d89" = 1.5
  dimension "d90" = 2
  dimension "d93" = 3.7
  text T0 "v1\n" font "Arial" height 6 bold align left top in box 13.2 x 5.4007 at (-27.7, -20) x (0, -1) y (1, 0) spacing 1 kerned
  text T1 "pen\nmount" font "Arial" height 3.7 bold align left top in box 12.5802 x 5 at (24.0828, -19.2154) x (-0.000531, -1) y (1, -0.000531) spacing 1 kerned
  constraint concentric A3 A8
  constraint concentric A2 A9
  constraint concentric A1 A10
  constraint concentric A0 A11
  constraint equal A8 A9
  constraint equal A8 A10
  constraint equal A8 A11
  measures "d76" diameter of A8
  measures "d88" distance of L30 L43
  measures "d89" distance of L39 L41
  measures "d90" distance of L38 L40
fillet "Fillet2" radius 0.25 4 faces at (-13.2587, 23.3258, 4.3333) (-13.2587, 30.3258, 4.3333) (16.7413, 30.3258, 4.3333) (16.7413, 23.3258, 4.3333) on bodies 1 in component "Pen Mount"
fillet "Fillet2" radius 0.25 4 faces at (-7.8557, -4.3145, 3.7317) (-8.3287, -20.2663, 3.7317) (10.1443, -4.3145, 3.7317) (9.6713, -20.2663, 3.7317) on bodies 1 in component "Pen Mount"
fillet "Fillet2'" radius 0.25 4 edges at (-6.7158, -5.086, 17.19) (11.2842, -5.086, 17.19) (11.2842, -22.086, 17.19) (-6.7158, -22.086, 17.19) on bodies 2 in component "Clamp"
extrude "Extrude4" add sketch "Mounting screw heads" along normal blind 0.2 text T0 T1 bodies 1 in component "Pen Mount"
component "Pen Mount" placed x (1, 0, 0) y (0, 1, 0) z (0, 0, 1) at (0, 0, 0)
component "Clamp" placed x (1, 0, 0) y (0, 1, 0) z (0, 0, 1) at (0, 0, 0)
equation "d8 = flexure_thickness"
equation "d9 = flexure_thickness"
equation "flexure_thickness = 2 * nozzle_diameter"
equation "d12 = flexure_clearance_push"
equation "d13 = flexure_clearance_pull"
equation "d14 = flexure_clearance_pull"
equation "flexure_clearance_pull = 1 mm"
equation "d16 = flexure_clearance_pull"
equation "d17 = flexure_clearance_pull"
equation "d18 = flexure_clearance_pull"
equation "d20 = flexure_thickness"
equation "flexure_clearance_push = 6 mm"
equation "d22 = flexure_clearance_push"
equation "nozzle_diameter = 0.4 mm"
equation "d36 = mount_thickness"
equation "BIC_pen_diameter_max = 8.533 mm"
equation "d40 = ( BIC_pen_diameter_max / 2 )"
equation "d42 = ( BIC_pen_diameter_min / 2 ) - 0.0 mm"
equation "BIC_pen_diameter_min = 7.39 mm"
equation "d48 = ( BIC_pen_diameter_min / 2 ) - 0.7 mm"
equation "mount_thickness = 6.5 mm"
